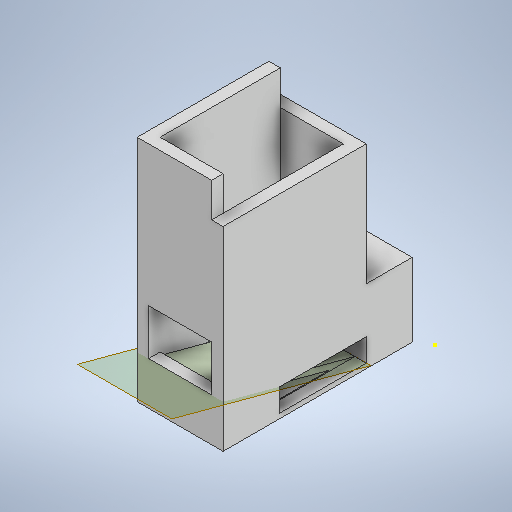
# Autodesk Inventor part: Semesterprojekt1magnetpakholder3.2
Saved by Autodesk Inventor 2027.1 (Build 311270010, 270A)
## iProperties
Created: 2026-10-29
Part Number: Semesterprojekt1magnetpakholder3.2
Material: Generic
Document SubType Name: Modeling
Designer: Sif Isaksen
Density: 1 g/cm^3
Appearance: Default
Author: Sif Isaksen
Autodesk Inventor part; units mm, degrees
ref_plane "YZ Plane" through (0, 0, 0) normal (1, 0, 0) x (0, 1, 0)
ref_plane "XZ Plane" through (0, 0, 0) normal (0, 1, 0) x (-1, 0, 0)
ref_plane "XY Plane" through (0, 0, 0) normal (0, 0, 1) x (1, 0, 0)
sketch "Sketch1" plane through (0, 0, 0) normal (0, 1, 0) x (-1, 0, 0)
  line L0 (15.411273, 32.528848) -> (4.411273, 32.528848)
  line L1 (4.411273, 32.528848) -> (4.411273, 11.528848)
  line L2 (4.411273, 11.528848) -> (15.411273, 11.528848)
  line L3 (15.411273, 11.528848) -> (15.411273, 32.528848)
  line L4 (17.411273, 34.528848) -> (2.411273, 34.528848)
  line L5 (2.411273, 34.528848) -> (2.411273, 9.528848)
  line L6 (2.411273, 9.528848) -> (17.411273, 9.528848)
  line L7 (17.411273, 9.528848) -> (17.411273, 34.528848)
  point P0 (0, 0)
  dimension "d0" = 11
  dimension "d1" = 21
  dimension "d2" = 15
  dimension "d3" = 25
  dimension "d4" = 2
  dimension "d5" = 2
  constraints: 16 end point, 4 parallel, 2 horizontal, 2 perpendicular
  measures "d0" distance of L2.end L1.end
  measures "d1" distance of L1.end L0.end
  measures "d2" distance of L6.end L5.end
  measures "d3" distance of L5.end L4.end
  measures "d4" distance between parallel lines of L7 L3
  measures "d5" distance between parallel lines of L4 L0
extrude "Extrusion1" add sketch "Sketch1" along normal blind 27
sketch "Sketch2" plane through (0, 27, 0) normal (0, 1, 0) x (1, 0, 0)
  line L0 (-15.411273, -32.528848) -> (-15.411273, -11.528848)
  line L1 (-17.411273, -34.528848) -> (-2.411273, -34.528848)
  line L2 (-15.411273, -32.528848) -> (-2.411273, -32.528848)
  line L3 (-2.411273, -32.528848) -> (-2.411273, -34.528848)
  line L4 (-2.411273, -34.528848) -> (-15.411273, -34.528848)
  line L5 (-15.411273, -34.528848) -> (-15.411273, -32.528848)
  line L6 (-17.411273, -9.528848) -> (-17.411273, -34.528848)
  line L7 (-15.411273, -11.528848) -> (-4.411273, -11.528848)
  line L8 (-17.411273, -34.528848) -> (-15.411273, -34.528848)
  line L9 (-15.411273, -34.528848) -> (-15.411273, -11.528848)
  line L10 (-15.411273, -11.528848) -> (-17.411273, -11.528848)
  line L11 (-17.411273, -11.528848) -> (-17.411273, -34.528848)
  point P0 (0, 0)
  constraints: 16 end point, 4 parallel, 2 horizontal, 2 perpendicular
extrude "Extrusion2" add sketch "Sketch2" along normal blind 6 contours L5 L1 L6 L10 L0
sketch "Sketch3" plane through (0, 27, 0) normal (0, 1, 0) x (1, 0, 0)
  line L0 (-15.411273, -34.528848) -> (-2.411273, -34.528848)
  line L1 (-4.411273, -32.528848) -> (-15.411273, -32.528848)
  line L2 (-15.411273, -34.528848) -> (-4.411273, -34.528848)
  line L3 (-4.411273, -34.528848) -> (-4.411273, -32.528848)
  line L4 (-4.411273, -32.528848) -> (-15.411273, -32.528848)
  line L5 (-15.411273, -32.528848) -> (-15.411273, -34.528848)
  point P0 (0, 0)
  point P1 (-4.411273, -34.528848)
  constraints: 8 end point, 2 parallel, 1 horizontal, 1 perpendicular
extrude "Extrusion3" add sketch "Sketch3" along normal blind 6
ref_plane "Work Plane1" through (-4.411273, 0, 32.528848) normal (0, -0.9659258, 0.258819) x (-1, 0, 0)
sketch "Sketch4" plane through (-4.411273, 0, 32.528848) normal (0, -0.9659258, 0.258819) x (-1, 0, 0)
  line L0 (0, 0) -> (11, 0) projected
  line L1 (0, 0) -> (11, 0)
  line L2 (11, 0) -> (11, 20.28)
  line L3 (11, 20.28) -> (0, 20.28)
  line L4 (0, 20.28) -> (0, 0)
  point P0 (-4.411273, 31.420454)
  dimension "d13" = 11
  dimension "d14" = 20.28
  constraints: 8 end point, 2 parallel, 1 horizontal, 1 perpendicular
  measures "d13" distance of L3.end L2.end
  measures "d14" distance of L2.end L1.end
extrude "Extrusion4" add sketch "Sketch4" along normal blind 1
sketch "Sketch6" plane through (-2.411273, 0, 34.528848) normal (0, 0, 1) x (1, 0, 0)
  line L0 (-13, 0.535898) -> (-0.36604, 0.535898)
  line L1 (-0.36604, 0.535898) -> (-14.36604, 0.535898)
  line L2 (-14.36604, 0.535898) -> (-14.36604, 6.535898)
  line L3 (-14.36604, 6.535898) -> (-0.36604, 6.535898)
  line L4 (-0.36604, 6.535898) -> (-0.36604, 0.535898)
  point P0 (2.411273, 0)
  dimension "d19" = 14
  dimension "d20" = 6
  constraints: 8 end point, 2 parallel, 1 horizontal, 1 perpendicular
  measures "d19" distance of L2.end L3.end
  measures "d20" distance of L1.end L2.end
extrude "Extrusion6" cut sketch "Sketch6" against normal blind 2
sketch "Sketch7" plane through (0, 0, 0) normal (0, -1, 0) x (1, 0, 0)
  line L0 (-4.411273, 32.787667) -> (-15.411273, 32.787667)
  line L1 (-15.411273, 11.528848) -> (-4.411273, 11.528848)
  line L2 (-15.411273, 32.787667) -> (-4.411273, 32.787667)
  line L3 (-4.411273, 32.787667) -> (-4.411273, 11.528848)
  line L4 (-4.411273, 11.528848) -> (-15.411273, 11.528848)
  line L5 (-15.411273, 11.528848) -> (-15.411273, 32.787667)
  line L6 (-17.411273, 9.528848) -> (-17.411273, 34.528848)
  line L7 (-2.411273, 34.528848) -> (-2.411273, 9.528848)
  line L8 (-17.411273, 34.528848) -> (-2.411273, 34.528848)
  line L9 (-2.411273, 34.528848) -> (-2.411273, 9.528848)
  line L10 (-2.411273, 9.528848) -> (-17.411273, 9.528848)
  line L11 (-17.411273, 9.528848) -> (-17.411273, 34.528848)
  point P0 (0, 0)
  constraints: 16 end point, 4 parallel, 2 horizontal, 2 perpendicular
extrude "Extrusion7" add sketch "Sketch7" along normal blind 7
sketch "Sketch9" plane through (-2.411273, 27, 9.528848) normal (0, 0, -1) x (-1, 0, 0)
  line L0 (2, -33.162831) -> (13.419198, -33.162831)
  line L1 (0, -34) -> (0, 0)
  line L2 (13.419198, -33.162831) -> (0, -33.162831)
  line L3 (0, -33.162831) -> (0, -29.162831)
  line L4 (0, -29.162831) -> (13.419198, -29.162831)
  line L5 (13.419198, -29.162831) -> (13.419198, -33.162831)
  point P0 (-2.411273, -27)
  dimension "d27" = 4
  constraints: 8 end point, 2 parallel, 1 horizontal, 1 perpendicular, 1 point on line
  measures "d27" distance of L2.end L3.end
extrude "Extrusion9" cut sketch "Sketch9" against normal blind 2
sketch "Sketch10" plane through (-2.411273, 27, 9.528848) normal (0, 0, -1) x (-1, 0, 0)
  line L0 (13.419198, -29.162831) -> (13.419198, -33.162831)
  line L1 (15, -34) -> (15, 0)
  line L2 (13.419198, -33.162831) -> (15, -33.162831)
  line L3 (15, -33.162831) -> (15, -29.162831)
  line L4 (15, -29.162831) -> (13.419198, -29.162831)
  line L5 (13.419198, -29.162831) -> (13.419198, -33.162831)
  point P0 (-2.411273, -27)
  dimension "d30" = 4
  constraints: 8 end point, 2 parallel, 1 horizontal, 1 perpendicular, 1 point on line
  measures "d30" distance of L3.end L2.end
extrude "Extrusion10" cut sketch "Sketch10" against normal blind 2
sketch "Sketch11" plane through (-17.411273, 27, 11.528848) normal (-1, 0, 0) x (0, 0, 1)
  line L0 (-2, -33.162831) -> (0, -33.162831)
  line L1 (0, -33.162831) -> (13.184692, -33.162831)
  line L2 (13.184692, -33.162831) -> (13.184692, -29.162831)
  line L3 (13.184692, -29.162831) -> (0, -29.162831)
  line L4 (0, -29.162831) -> (0, -33.162831)
  point P0 (-11.528848, -27)
  dimension "d33" = 4
  constraints: 8 end point, 2 parallel, 1 horizontal, 1 perpendicular
  measures "d33" distance of L2.end L1.end
extrude "Extrusion11" cut sketch "Sketch11" against normal blind 2
sketch "Sketch12" plane through (-2.411273, 27, 34.528848) normal (1, 0, 0) x (0, 0, -1)
  line L0 (23, -33.162831) -> (23, -32.626933)
  line L1 (23, -33.162831) -> (9.877396, -33.162831)
  line L2 (9.877396, -33.162831) -> (9.877396, -29.162831)
  line L3 (9.877396, -29.162831) -> (23, -29.162831)
  line L4 (23, -29.162831) -> (23, -33.162831)
  point P0 (34.528848, -27)
  dimension "d36" = 4
  constraints: 8 end point, 2 parallel, 1 horizontal, 1 perpendicular
  measures "d36" distance of L1.end L2.end
extrude "Extrusion12" cut sketch "Sketch12" against normal blind 2
sketch "Sketch13" plane through (-17.411273, 33, 34.528848) normal (0, 0, 1) x (1, 0, 0)
  line L0 (0.63396, -26.464102) -> (14.63396, -26.464102)
  line L1 (2, -32.464102) -> (13, -32.464102)
  line L2 (14.63396, -26.464102) -> (13, -26.464102)
  line L3 (13, -26.464102) -> (13, -32.464102)
  line L4 (13, -32.464102) -> (14.63396, -32.464102)
  line L5 (14.63396, -32.464102) -> (14.63396, -26.464102)
  point P0 (17.411273, -33)
  constraints: 8 end point, 2 parallel, 1 horizontal, 1 perpendicular
extrude "Extrusion13" add sketch "Sketch13" against normal blind 2
sketch "Sketch14" plane through (-17.411273, 33, 34.528848) normal (0, 0, 1) x (1, 0, 0)
  line L0 (0.63396, -26.464102) -> (2, -26.464102)
  line L1 (2, -32.464102) -> (0.63396, -32.464102)
  line L2 (0.63396, -26.464102) -> (2, -26.464102)
  line L3 (2, -26.464102) -> (2, -32.464102)
  line L4 (2, -32.464102) -> (0.63396, -32.464102)
  line L5 (0.63396, -32.464102) -> (0.63396, -26.464102)
  point P0 (17.411273, -33)
  constraints: 8 end point, 2 parallel, 1 horizontal, 1 perpendicular
extrude "Extrusion14" add sketch "Sketch14" against normal blind 2
sketch "Sketch15" plane through (-17.411273, 33, 34.528848) normal (0, 0, 1) x (1, 0, 0)
  line L0 (2, -26.464102) -> (13, -26.464102)
  line L1 (2, -26.464102) -> (13, -26.464102)
  line L2 (13, -26.464102) -> (13, -24.464102)
  line L3 (13, -24.464102) -> (2, -24.464102)
  line L4 (2, -24.464102) -> (2, -26.464102)
  point P0 (17.411273, -33)
  dimension "d43" = 11
  dimension "d44" = 2
  constraints: 8 end point, 2 parallel, 1 horizontal, 1 perpendicular
  measures "d43" distance of L3.end L2.end
  measures "d44" distance of L2.end L1.end
extrude "Extrusion15" cut sketch "Sketch15" against normal blind 2
sketch "Sketch16" plane through (0, -7, 0) normal (0, -1, 0) x (1, 0, 0)
  line L0 (-4.411273, 32.787667) -> (-15.411273, 32.787667)
  line L1 (-15.411273, 32.528848) -> (-15.411273, 11.528848)
  line L2 (-4.411273, 32.787667) -> (-15.411273, 32.787667)
  line L3 (-15.411273, 32.787667) -> (-15.411273, 11.528848)
  line L4 (-15.411273, 11.528848) -> (-4.411273, 11.528848)
  line L5 (-4.411273, 11.528848) -> (-4.411273, 32.787667)
  point P0 (0, 0)
  constraints: 8 end point, 2 parallel, 1 horizontal, 1 perpendicular
extrude "Extrusion16" add sketch "Sketch16" against normal blind 1
sketch "Sketch17" plane through (-4.411273, 0, 32.528848) normal (0, -0.9659258, 0.258819) x (-1, 0, 0)
  line L0 (13, 23.811352) -> (-2, 23.811352)
  line L1 (0, 20.28) -> (11, 20.28)
  line L2 (11, 20.28) -> (11, 23.811352)
  line L3 (11, 23.811352) -> (0, 23.811352)
  line L4 (0, 23.811352) -> (0, 20.28)
  point P0 (-4.411273, 31.420454)
  point P1 (0, 23.811352)
  dimension "d49" = 11
  constraints: 8 end point, 2 parallel, 1 horizontal, 1 perpendicular, 1 point on line
  measures "d49" distance of L3.end L2.end
extrude "Extrusion17" add sketch "Sketch17" along normal blind 1
sketch "Sketch18" plane through (0, -7, 0) normal (0, -1, 0) x (1, 0, 0)
  point P0 (0, 0)
sketch "Sketch19" plane through (0, -7, 0) normal (0, -1, 0) x (1, 0, 0)
  point P0 (0, 0)
sketch "Sketch20" plane through (-17.411273, 27, 11.528848) normal (-1, 0, 0) x (0, 0, 1)
  line L0 (-1.775681, -34) -> (-1.260652, -34)
  line L1 (-1.741181, -34.128757) -> (-1.260652, -34)
  line L2 (-1.775681, -34) -> (-1.741181, -34.128757)
  line L3 (-1.741181, -34.128757) -> (-1.260652, -34)
  line L4 (-1.260652, -34) -> (-1.775681, -34)
  line L5 (-2, -34) -> (23, -34)
  point P0 (-11.528848, -27)
  constraints: 6 end point, 2 collinear, 1 perpendicular
extrude "Extrusion18" cut sketch "Sketch20" against normal blind 15
sketch "Sketch21" plane through (-2.411273, 27, 9.528848) normal (0, 0, -1) x (-1, 0, 0)
  line L0 (0, -33.162831) -> (0, -29.162831)
  line L1 (0, -29.162831) -> (15, -29.162831)
  line L2 (15, -29.162831) -> (15, -34)
  line L3 (15, -34) -> (0, -34)
  line L4 (0, -34) -> (0, -29.162831)
  point P0 (-2.411273, -27)
  constraints: 8 end point, 2 parallel, 1 horizontal, 1 perpendicular
extrude "Extrusion19" add sketch "Sketch21" along normal blind 8
sketch "Sketch22" plane through (-2.411273, 27, 1.528848) normal (0, 0, -1) x (-1, 0, 0)
  circle A0 centre (7.256698, -31.561103) radius 1
  point P0 (-2.411273, -27)
  dimension "d56" = 2
  constraints: 1 centre point
  measures "d56" diameter of A0
extrude "Extrusion20" cut sketch "Sketch22" against normal blind 8
sketch "Sketch23" plane through (-17.411273, -2.162831, 9.528848) normal (0, 1, 0) x (1, 0, 0)
  line L0 (0, 8) -> (15, 8) projected
  line L1 (15, 0) -> (0, 0) projected
  line L2 (0, 8) -> (15, 8)
  line L3 (15, 8) -> (15, 0)
  line L4 (15, 0) -> (0, 0)
  line L5 (0, 0) -> (0, 8)
  point P0 (17.411273, 9.528848)
  constraints: 8 end point, 2 parallel, 1 horizontal, 1 perpendicular
extrude "Extrusion21" add sketch "Sketch23" along normal blind 8
body "Solid1"
